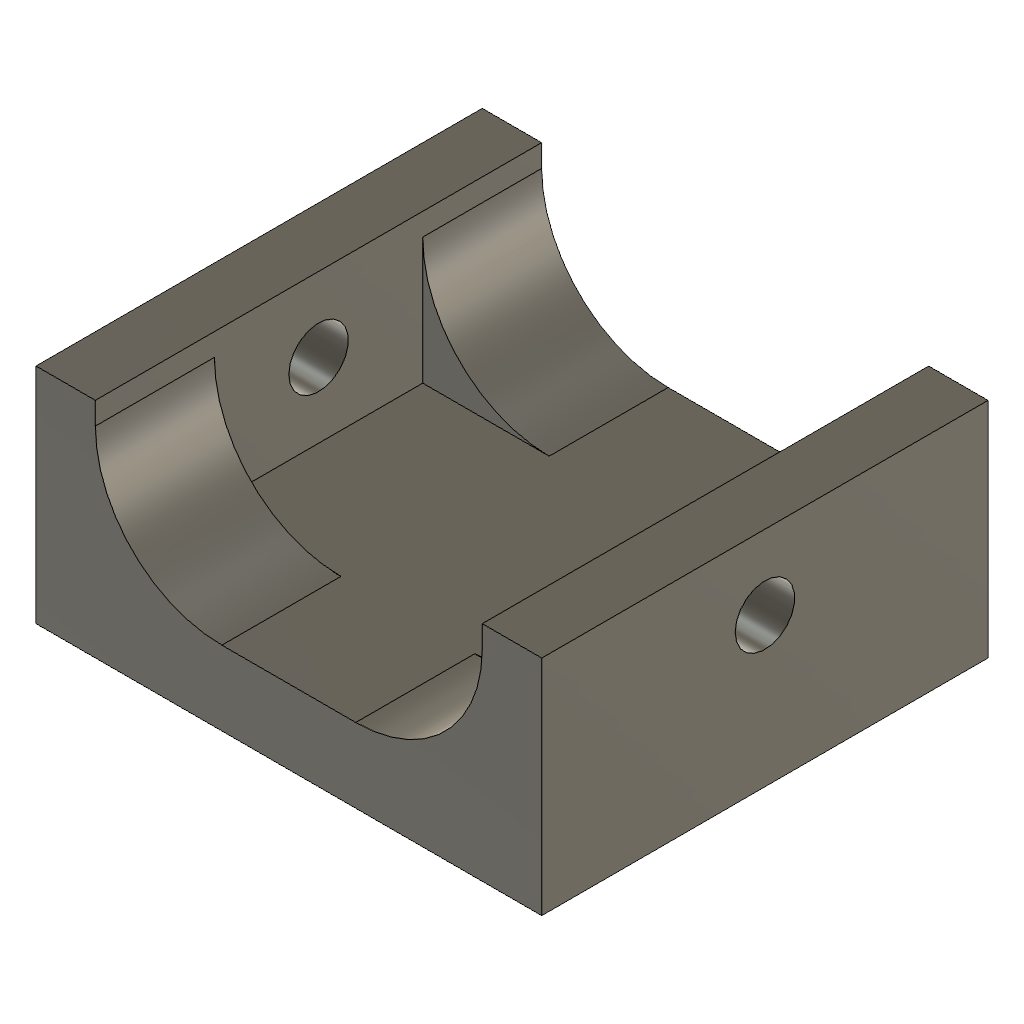
Aris Chute test 1 TOP (Autodesk Fusion 360 design; units mm, degrees)
Autodesk Fusion 360 part; units mm, degrees
sketch "Sketch1" plane through (0, 0, 0) normal (0, 0, 1) x (1, 0, 0)
  line L0 (17, 15) -> (-17, 15)
  line L1 (-17, 15) -> (-17, -15)
  line L2 (-17, -15) -> (17, -15)
  line L3 (17, -15) -> (17, 15)
  line L4 (17, 15) -> (-17, -15) construction
  line L5 (-17, 15) -> (17, -15) construction
  dimension "d1" = 34
  dimension "d2" = 30
  constraint horizontal L0
  constraint perpendicular L0 L1
  constraint parallel L0 L2
  constraint parallel L1 L3
  constraint coincident L4 origin
  constraint coincident L5 origin
  measures "d1" distance of L1.end L2.end
  measures "d2" distance of L0.end L1.end
extrude "Extrude1" add sketch "Sketch1" along normal blind 5
sketch "Sketch2" plane through (0, 0, 5) normal (0, 0, 1) x (-1, 0, 0)
  line L0 (-17, 15) -> (-17, -15)
  line L1 (-17, -15) -> (17, -15)
  line L2 (17, -15) -> (17, 15)
  line L3 (17, 15) -> (-17, 15)
  line L4 (-17, -15) -> (-13, -15)
  line L5 (-13, -15) -> (-13, 15)
  line L6 (-13, 15) -> (-17, 15)
  line L7 (-17, 15) -> (-17, -15)
  line L8 (17, -15) -> (13, -15)
  line L9 (13, -15) -> (13, 15)
  line L10 (13, 15) -> (17, 15)
  line L11 (17, 15) -> (17, -15)
  dimension "d5" = 4
  dimension "d6" = 4
  constraint horizontal L4
  constraint vertical L5
  constraint horizontal L6
  constraint vertical L7
  constraint coincident L0.end L1.start
  constraint horizontal L8
  constraint vertical L9
  constraint horizontal L10
  constraint vertical L11
  constraint coincident L1.end L2.start
  measures "d5" distance of L0.end L4.end
  measures "d6" distance of L1.end L8.end
extrude "Extrude2" add sketch "Sketch2" along normal blind 10 contours L0 L1 L3 L4 L5 L6 L7 | L1 L2 L3 L8 L9 L10 L11
sketch "Sketch3" plane through (17, 0, 0) normal (1, 0, 0) x (0, 1, 0)
  line L0 (-15, 0) -> (15, 0)
  line L1 (15, 0) -> (15, 15)
  line L2 (15, 15) -> (-15, 15)
  line L3 (-15, 15) -> (-15, 0)
  line L4 (-15, 0) -> (15, 0)
  line L5 (15, 0) -> (15, 5)
  line L6 (15, 5) -> (-15, 5)
  line L7 (-15, 5) -> (-15, 0)
  line L8 (0, 5) -> (0, 15)
  circle A0 centre (0, 10) radius 2
  point P0 (15, 5)
  dimension "d9" = 4
  constraint horizontal L4
  constraint vertical L5
  constraint horizontal L6
  constraint vertical L7
  constraint coincident P0 L5.end
  constraint coincident L0.start L3.end
  constraint midpoint L6 L8.start
  constraint midpoint L2 L8.end
  constraint midpoint L8 A0.centre
  measures "d9" diameter of A0
extrude "Extrude3" cut sketch "Sketch3" against normal blind 37 contours L8 A0 | L8 A0
sketch "Sketch4" plane through (-13, 0, 0) normal (1, 0, 0) x (0, 1, 0)
  circle A0 centre (0, 10) radius 2
  line L0 (-15, 5) -> (15, 5)
  line L1 (15, 5) -> (15, 15)
  line L2 (15, 15) -> (-15, 15)
  line L3 (-15, 15) -> (-15, 5)
  line L4 (-15, 15) -> (-7, 15)
  line L5 (-7, 15) -> (-7, 5)
  line L6 (-7, 5) -> (-15, 5)
  line L7 (-15, 5) -> (-15, 15)
  line L8 (15, 15) -> (7, 15)
  line L9 (7, 15) -> (7, 5)
  line L10 (7, 5) -> (15, 5)
  line L11 (15, 5) -> (15, 15)
  dimension "d12" = 8
  dimension "d13" = 8
  constraint horizontal L4
  constraint vertical L5
  constraint horizontal L6
  constraint vertical L7
  constraint coincident L2.end L3.start
  constraint horizontal L8
  constraint vertical L9
  constraint horizontal L10
  constraint vertical L11
  constraint coincident L1.end L2.start
  measures "d12" distance of L2.end L4.end
  measures "d13" distance of L1.end L8.end
extrude "Extrude4" cut sketch "Sketch4" against normal blind 1 contours L0 L2 L5 L9
fillet "Fillet1" radius 8.5 1 edges at (-13, -11, 5)
fillet "Fillet2" radius 8.5 1 edges at (-13, 11, 5)
sketch "Sketch5" plane through (13, 0, 0) normal (-1, 0, 0) x (0, -1, 0)
  circle A0 centre (0, 10) radius 2
  line L0 (-15, 5) -> (15, 5)
  line L1 (15, 5) -> (15, 15)
  line L2 (15, 15) -> (-15, 15)
  line L3 (-15, 15) -> (-15, 5)
  line L4 (-15, 15) -> (-7, 15)
  line L5 (-7, 15) -> (-7, 5)
  line L6 (-7, 5) -> (-15, 5)
  line L7 (-15, 5) -> (-15, 15)
  line L8 (15, 15) -> (7, 15)
  line L9 (7, 15) -> (7, 5)
  line L10 (7, 5) -> (15, 5)
  line L11 (15, 5) -> (15, 15)
  dimension "d20" = 8
  dimension "d21" = 8
  constraint horizontal L4
  constraint vertical L5
  constraint horizontal L6
  constraint vertical L7
  constraint coincident L2.end L3.start
  constraint horizontal L8
  constraint vertical L9
  constraint horizontal L10
  constraint vertical L11
  constraint coincident L1.end L2.start
  measures "d20" distance of L2.end L4.end
  measures "d21" distance of L1.end L8.end
extrude "Extrude5" cut sketch "Sketch5" against normal blind 1 contours L0 L2 L5 L9
fillet "Fillet3" radius 8.5 1 edges at (13, 11, 5)
fillet "Fillet4" radius 8.5 1 edges at (13, -11, 5)
extrude "Extrude6" add 1 faces at (-14, -5.3333, 10) along direction (1, 0, 0) blind 1
extrude "Extrude7" add 1 faces at (14, 5.3333, 10) along direction (-1, 0, 0) blind 1
